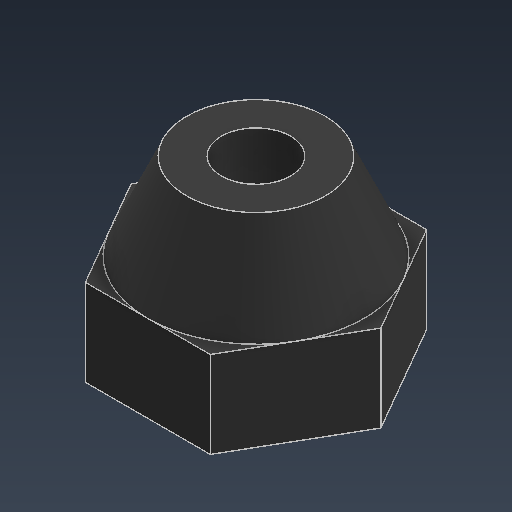
# Autodesk Inventor part: 2020 FootEnd_FOOT
Saved by Autodesk Inventor 2026.2 (Build 302298010, 298A)
## iProperties
Created: 2026-05-13
Part Number: 2020 FootEnd_FOOT
Material: 고무
Document SubType Name: Modeling
Designer: khw
Density: 0.93 g/cm^3
Appearance: 고무 - 검은색
Author: khw
Autodesk Inventor part; units mm, degrees
ref_plane "YZ Plane" through (0, 0, 0) normal (1, 0, 0) x (0, 1, 0)
ref_plane "XZ Plane" through (0, 0, 0) normal (0, 1, 0) x (-1, 0, 0)
ref_plane "XY Plane" through (0, 0, 0) normal (0, 0, 1) x (1, 0, 0)
sketch "스케치1" plane through (0, 0, 0) normal (0, 1, 0) x (-1, 0, 0)
  line L0 (14.4338, 0) -> (7.2169, -12.5)
  line L1 (7.2169, -12.5) -> (-7.2169, -12.5)
  line L2 (-7.2169, -12.5) -> (-14.4338, 0)
  line L3 (-14.4338, 0) -> (-7.2169, 12.5)
  line L4 (-7.2169, 12.5) -> (7.2169, 12.5)
  line L5 (7.2169, 12.5) -> (14.4338, 0)
  circle A0 centre (0, 0) radius 4
  line L6 (0, 0) -> (14.4338, 0) construction
  dimension "d0" = 8
  dimension "d1" = 25
  constraints: 14 end point, 2 coincident, 1 centre point, 1 horizontal, 13 other
  measures "d0" diameter of A0
  measures "d1" distance between parallel lines of L4 L1
extrude "돌출1" add sketch "스케치1" along normal blind 20
sketch "스케치2" plane through (0, 0, 0) normal (1, 0, 0) x (0, 1, 0)
  line L0 (20, -12.5) -> (20, 0) projected
  line L1 (20, -8) -> (10, -12.5)
  line L2 (0, -12.5) -> (20, -12.5) projected
  line L3 (0, 0) -> (20, 0)
  line L4 (20, -8) -> (32.7603, -8)
  line L5 (32.7603, -8) -> (32.7603, -26.5445)
  line L6 (32.7603, -26.5445) -> (20, -26.5445)
  line L7 (20, -26.5445) -> (20, -8)
  line L8 (10, -12.5) -> (20, -12.5)
  line L9 (20, -12.5) -> (20, -34.7222)
  line L10 (20, -34.7222) -> (10, -34.7222)
  line L11 (10, -34.7222) -> (10, -12.5)
  dimension "d4" = 8
  dimension "d5" = 10
  constraints: 20 end point, 4 parallel, 3 perpendicular, 2 horizontal, 1 midpoint, 1 point on line
  measures "d4" distance of L0.end L1.start
  measures "d5" distance of L2.start L1.end
revolve "회전1" cut sketch "스케치2" angle 360 about axis through (0, 0, 0) along (0, 1, 0)
sketch "스케치3" plane through (0, 0, 0) normal (0, -1, 0) x (1, 0, 0)
  circle A0 centre (0, 0) radius 7.5
  dimension "d7" = 15
  constraints: 1 centre point, 1 coincident
  measures "d7" diameter of A0
extrude "돌출2" cut sketch "스케치3" against normal blind 10
